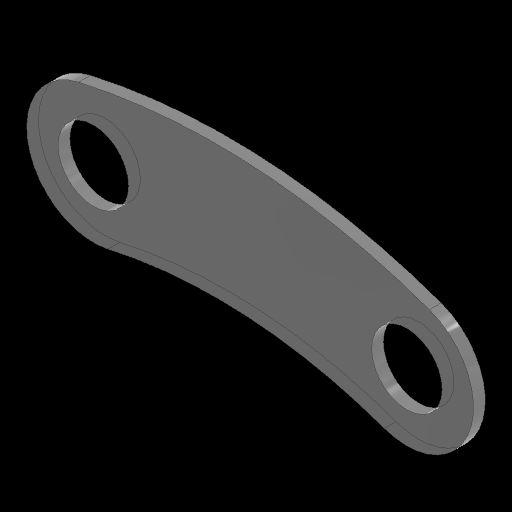
# Autodesk Inventor part: Part3
Saved by Autodesk Inventor 2027.1 (Build 311270010, 270A)
## iProperties
Created: 2026-11-12
Part Number: Part3
Material: Polycarbonate, Clear
Document SubType Name: Modeling
Designer: Stanley Ruangsuwan
Density: 1.2 g/cm^3
Appearance: Polycarbonate - Clear
Author: Stanley Ruangsuwan
Autodesk Inventor part; units mm, degrees
ref_plane "YZ Plane" through (0, 0, 0) normal (1, 0, 0) x (0, 1, 0)
ref_plane "XZ Plane" through (0, 0, 0) normal (0, 1, 0) x (-1, 0, 0)
ref_plane "XY Plane" through (0, 0, 0) normal (0, 0, 1) x (1, 0, 0)
sketch "Sketch1" plane through (0, 0, 0) normal (0, 0, 1) x (1, 0, 0)
  circle A0 centre (0, 0) radius 14.2875
  circle A1 centre (127, -7.8621) radius 14.2875
  arc A2 (131.8419, 5.58) -> (-3.1469, 13.9366) centre (50.0277, -221.5542) ccw construction
  arc A3 (122.1581, -21.3042) -> (3.1469, -13.9366) centre (50.0277, -221.5542) ccw construction
  circle A4 centre (0, 0) radius 26.9875
  arc A5 (136.1457, 17.5285) -> (-5.9442, 26.3247) centre (50.0277, -221.5542) ccw
  arc A6 (117.8543, -33.2527) -> (5.9442, -26.3247) centre (50.0277, -221.5542) ccw
  circle A7 centre (127, -7.8621) radius 26.9875
  point P0 (136.1457, 17.5285)
  point P1 (-5.9442, 26.3247)
  point P2 (5.9442, -26.3247)
  point P3 (117.8543, -33.2527)
  dimension "d0" = 28.575
  dimension "d1" = 28.575
  dimension "d2" = 212.8447
  dimension "d3" = 127
  dimension "d4" = 7.8621
  dimension "d5" = 12.7
  dimension "d6" = 12.7
  dimension "d7" = 12.7
  dimension "d8" = 12.7
  constraints: 12 point on circle, 8 centre point, 4 tangent, 2 coincident
  measures "d0" diameter of A0
  measures "d1" diameter of A1
  measures "d2" radius of A3
  measures "d3" horizontal distance of A7.centre A4.centre
  measures "d4" vertical distance of point (0, 0) A7.centre
  measures "d5" radial gap between concentric circles of A0 A4
  measures "d6" radial gap between concentric circles of A2 A5
  measures "d7" radial gap between concentric circles of A3 A6
  measures "d8" radial gap between concentric circles of A1 A7
extrude "Extrusion1" add sketch "Sketch1" along normal blind 4.7625
body "Solid1"
